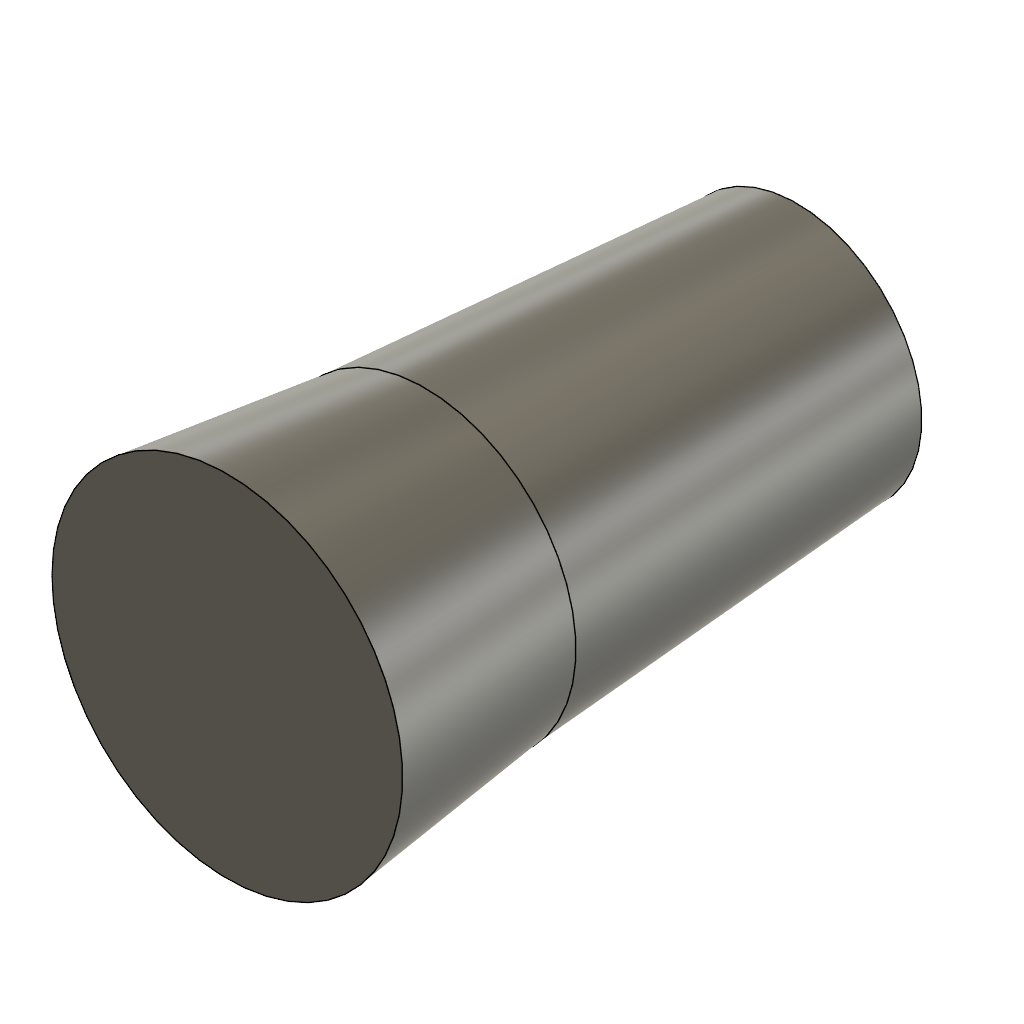
placement_edit_second (Autodesk Fusion 360 design; units mm, degrees)
part number: 2026-11-27-16-39-48-165
Autodesk Fusion 360 part; units mm, degrees
sketch "CircularProfile" plane through (0, 0, 0) normal (0, 0, 1) x (1, 0, 0)
  circle A0 centre (-14, 21) radius 13
extrude "TwoSidedDraft" add sketch "CircularProfile" along normal blind 17 draft 7 and the other way blind 32 draft -4
